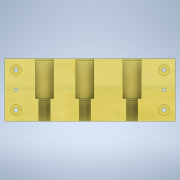
# Autodesk Inventor part: P1_V4_001_mirror
Saved by Autodesk Inventor 2020 (Build 240168000, 168)
## iProperties
Created: 2022-06-02
Part Number: P1_V4_001_mirror
Material: Wood (Maple)
Document SubType Name: Modeling
Designer: drago
Density: 0.67 g/cm^3
Appearance: Natural Maple - Glossy Dark Tint(1)
Author: drago
Autodesk Inventor part; units mm, degrees
ref_plane "YZ Plane" through (0, 0, 0) normal (1, 0, 0) x (0, 1, 0)
ref_plane "XZ Plane" through (0, 0, 0) normal (0, 1, 0) x (-1, 0, 0)
sketch "Sketch_dreptunghi_mare" plane through (0, 0, 0) normal (0, 0, 1) x (1, 0, 0)
  line L0 (0, 0) -> (-150, 0)
  line L1 (-150, 0) -> (-150, 55)
  line L2 (-150, 55) -> (0, 55)
  line L3 (0, 55) -> (0, 0)
  dimension "d77" = 150
  dimension "d78" = 55
  constraints: 8 end point, 2 parallel, 1 horizontal, 1 perpendicular
  measures "d77" distance of L1.end L2.end
  measures "d78" distance of L0.end L1.end
extrude "Extrude_monobloc" add sketch "Sketch_dreptunghi_mare" along normal blind 40
sketch "Sketch_gauri_mici_jos" plane through (-150, 55, 0) normal (0, 1, 0) x (1, 0, 0)
  line L0 (150, 0) -> (0, 0) projected
  line L1 (0, 0) -> (0, -40) projected
  line L2 (150, -40) -> (0, -40) projected
  line L3 (150, 0) -> (150, -40) projected
  line L4 (0, 0) -> (0, -40) construction
  line L5 (0, -10.5) -> (150, -10.5) construction
  line L6 (150, 0) -> (150, -40) construction
  circle A0 centre (35, -10.5) radius 7.5
  circle A1 centre (70.5, -10.5) radius 7.5
  circle A2 centre (112, -10.5) radius 7.5
  line L7 (0, 0) -> (150, 0) construction
  line L8 (15, 0) -> (15, -40) construction
  line L9 (0, -40) -> (150, -40) construction
  line L10 (135, 0) -> (135, -40) construction
  line L11 (70.5, -10.5) -> (112, -10.5) construction
  line L12 (35, -10.5) -> (35, -33.9967)
  line L13 (76.5, -33.9967) -> (70.5, -10.5)
  line L14 (112, -33.9967) -> (112, -10.5)
  dimension "d214" = 10.5
  dimension "d215" = 15
  dimension "d216" = 15
  dimension "d217" = 15
  dimension "d218" = 15
  dimension "d219" = 15
  dimension "d220" = 20
  dimension "d221" = 23
  dimension "d240" = 41.5
  constraints: 14 end point, 9 point on line, 3 centre point, 3 perpendicular, 1 collinear, 1 vertical
  measures "d214" distance between parallel lines of L5 L0
  measures "d215" diameter of A0
  measures "d216" diameter of A1
  measures "d217" diameter of A2
  measures "d218" distance between parallel lines of L1 L8
  measures "d219" distance between parallel lines of L3 L10
  measures "d220" distance from line of L8 L12.start
  measures "d221" distance from line of L10 L11.end
  measures "d240" distance of L11.end L11.start
extrude "Extrude_Cut_gauri_mici_jos" cut sketch "Sketch_gauri_mici_jos" against normal blind 20 contours A0 | A1 | A2
ref_plane "Offset_schimbare_sectiune_gauri" through (-150, 35, 40) normal (0, 1, 0) x (1, 0, 0)
sketch "Sketch_gauri_mari_sus" plane through (-150, 35, 40) normal (0, 1, 0) x (1, 0, 0)
  line L0 (150, 40) -> (0, 40) projected
  line L1 (0, 40) -> (0, 0) projected
  line L2 (150, 0) -> (0, 0) projected
  line L3 (150, 40) -> (150, 0) projected
  circle A0 centre (112, 29.5) radius 7.5 projected
  circle A1 centre (70.5, 29.5) radius 7.5 projected
  circle A2 centre (35, 29.5) radius 7.5 projected
  line L4 (150, 40) -> (0, 40) projected
  line L5 (0, 40) -> (0, 0) projected
  line L6 (150, 0) -> (0, 0) projected
  line L7 (150, 40) -> (150, 0) projected
  circle A3 centre (35, 29.5) radius 10.5
  circle A4 centre (70.5, 29.5) radius 10.5
  circle A5 centre (112, 29.5) radius 10.5
  dimension "d223" = 21
  dimension "d224" = 21
  dimension "d225" = 21
  constraints: 3 centre point, 3 concentric
  measures "d223" diameter of A3
  measures "d224" diameter of A4
  measures "d225" diameter of A5
extrude "Extrude_Cut_gauri_mari_sus" cut sketch "Sketch_gauri_mari_sus" against normal up to surface (35 mm away) contours A5 | A4 | A3 | A0 | A1 | A2
sketch "Sketch_Negrese_prins_in_perete" plane through (0, 0, 0) normal (0, 0, -1) x (-1, 0, 0)
  line L0 (0, 55) -> (150, 55) projected
  line L1 (0, 0) -> (0, 55) projected
  line L2 (150, 55) -> (150, 0) projected
  circle A0 centre (10, 10) radius 4.75
  circle A1 centre (10, 45) radius 4.75
  circle A2 centre (140, 45) radius 4.75
  circle A3 centre (140, 10) radius 4.75
  line L3 (150, 0) -> (115, 0) projected
  line L4 (38, 0) -> (0, 0) projected
  line L5 (38, 35) -> (38, 0) projected
  line L6 (79.5, 0) -> (38, 0) projected
  line L7 (79.5, 35) -> (79.5, 0) projected
  line L8 (115, 0) -> (79.5, 0) projected
  line L9 (115, 35) -> (115, 0) projected
  dimension "d127" = 9.5
  dimension "d128" = 9.5
  dimension "d129" = 9.5
  dimension "d130" = 9.5
  dimension "d131" = 10
  dimension "d134" = 10
  dimension "d136" = 10
  dimension "d138" = 10
  dimension "d189" = 10
  dimension "d190" = 10
  constraints: 4 centre point
  measures "d127" diameter of A3
  measures "d128" diameter of A2
  measures "d129" diameter of A1
  measures "d130" diameter of A0
  measures "d131" distance from line of L2 A3.centre
  measures "d134" distance from line of L2 A2.centre
  measures "d136" distance from line of L1 A0.centre
  measures "d138" distance from line of L1 A1.centre
  measures "d189" distance from line of L0 A2.centre
  measures "d190" distance from line of L0 A1.centre
extrude "Extrude_Cut_loc_cap_negrese(fixare)" cut sketch "Sketch_Negrese_prins_in_perete" against normal blind 30 contours A0 | A1 | A2 | A3
sketch "Sketch_corp_negrese_fixare_perete" plane through (0, 0, 0) normal (0, 0, -1) x (-1, 0, 0)
  circle A0 centre (10, 45) radius 4.75 projected
  circle A1 centre (140, 45) radius 4.75 projected
  circle A2 centre (10, 10) radius 4.75 projected
  circle A3 centre (140, 10) radius 4.75 projected
  line L0 (0, 55) -> (150, 55) projected
  line L1 (0, 0) -> (0, 55) projected
  line L2 (150, 55) -> (150, 0) projected
  circle A4 centre (140, 10) radius 2
  circle A5 centre (140, 45) radius 2
  circle A6 centre (10, 45) radius 2
  circle A7 centre (10, 10) radius 4.75 projected
  circle A8 centre (10, 10) radius 2
  line L3 (150, 0) -> (115, 0) projected
  line L4 (38, 0) -> (0, 0) projected
  line L5 (38, 35) -> (38, 0) projected
  line L6 (79.5, 0) -> (38, 0) projected
  line L7 (79.5, 35) -> (79.5, 0) projected
  line L8 (115, 0) -> (79.5, 0) projected
  line L9 (115, 35) -> (115, 0) projected
  dimension "d141" = 4
  dimension "d142" = 4
  dimension "d143" = 4
  dimension "d144" = 4
  constraints: 4 centre point, 4 coincident
  measures "d141" diameter of A4
  measures "d142" diameter of A5
  measures "d143" diameter of A6
  measures "d144" diameter of A8
extrude "Extrude_cut_corp_negrese(fixare)" cut sketch "Sketch_corp_negrese_fixare_perete" against normal up to next contours A4 | A5 | A6 | A8
sketch "Sketch_gaura_prins_plexi" plane through (0, 0, 0) normal (0, 0, -1) x (-1, 0, 0)
  line L0 (0, 55) -> (150, 55) projected
  line L1 (0, 0) -> (0, 55) projected
  line L2 (150, 0) -> (115, 0) projected
  circle A0 centre (10, 45) radius 4.75 projected
  circle A1 centre (10, 10) radius 4.75 projected
  circle A2 centre (140, 45) radius 4.75 projected
  circle A3 centre (140, 10) radius 4.75 projected
  line L3 (150, 55) -> (150, 0) projected
  line L4 (0, 55) -> (150, 55) projected
  circle A4 centre (10, 45) radius 2 construction
  circle A5 centre (140, 10) radius 2 construction
  circle A6 centre (140, 45) radius 2 construction
  circle A7 centre (140, 27.5) radius 1.7
  circle A8 centre (10, 27.5) radius 1.7
  line L5 (150, 55) -> (150, 0) projected
  line L6 (150, 0) -> (115, 0) projected
  line L7 (0, 0) -> (0, 55) projected
  line L8 (10, 45) -> (10, 27.5) construction
  line L9 (10, 10) -> (10, 27.5) construction
  circle A9 centre (140, 45) radius 2 construction
  line L10 (140, 45) -> (140, 27.5) construction
  circle A10 centre (140, 10) radius 2 construction
  line L11 (140, 27.5) -> (140, 10) construction
  line L12 (38, 0) -> (0, 0) projected
  line L13 (38, 35) -> (38, 0) projected
  line L14 (79.5, 0) -> (38, 0) projected
  line L15 (79.5, 35) -> (79.5, 0) projected
  line L16 (115, 0) -> (79.5, 0) projected
  line L17 (115, 35) -> (115, 0) projected
  line L18 (38, 0) -> (0, 0) projected
  line L19 (38, 35) -> (38, 0) projected
  line L20 (79.5, 0) -> (38, 0) projected
  line L21 (79.5, 35) -> (79.5, 0) projected
  line L22 (115, 0) -> (79.5, 0) projected
  line L23 (115, 35) -> (115, 0) projected
  dimension "d155" = 3.4
  dimension "d156" = 3.4
  constraints: 8 end point, 3 collinear, 3 vertical, 2 centre point, 1 coincident
  measures "d155" diameter of A7
  measures "d156" diameter of A8
extrude "Extrude_cut_gaura_prins_plexi" cut sketch "Sketch_gaura_prins_plexi" against normal up to surface (40 mm away) contours A7 | A8
sketch "deschiderea_sa_se_vada_cuiele" plane through (0, 0, 0) normal (0, 0, -1) x (-1, 0, 0)
  line L0 (125.5, 0) -> (104.5, 0) projected
  line L1 (90, 0) -> (69, 0) projected
  line L2 (48.5, 0) -> (27.5, 0) projected
  line L3 (125.5, 35) -> (104.5, 35) projected
  line L4 (90, 35) -> (69, 35) projected
  line L5 (48.5, 35) -> (27.5, 35) projected
  line L6 (104.5, 0) -> (125.5, 0)
  line L7 (150, 0) -> (115, 0) construction
  line L8 (125.5, 35) -> (104.5, 35)
  line L9 (107, 35) -> (123, 35)
  line L10 (123, 35) -> (123, 0)
  line L11 (123, 0) -> (107, 0)
  line L12 (107, 0) -> (107, 35)
  line L13 (107, 35) -> (123, 0)
  line L14 (123, 35) -> (107, 0)
  line L15 (115, 0) -> (79.5, 0) projected
  line L16 (115, 0) -> (115, 17.5)
  line L17 (115, 35) -> (115, 0) projected
  line L18 (115, 35) -> (115, 17.5)
  line L19 (71.5, 35) -> (87.5, 35)
  line L20 (87.5, 35) -> (87.5, 0)
  line L21 (87.5, 0) -> (71.5, 0)
  line L22 (71.5, 0) -> (71.5, 35)
  line L23 (79.5, 35) -> (79.5, 0) projected
  line L24 (71.5, 35) -> (87.5, 0)
  line L25 (87.5, 35) -> (71.5, 0)
  line L26 (79.5, 0) -> (38, 0) projected
  line L27 (30, 35) -> (46, 35)
  line L28 (46, 35) -> (46, 0)
  line L29 (46, 0) -> (30, 0)
  line L30 (30, 0) -> (30, 35)
  line L31 (38, 35) -> (38, 0) projected
  line L32 (30, 35) -> (46, 0)
  line L33 (46, 35) -> (30, 0)
  point P0 (79.5, 17.5)
  point P1 (38, 17.5)
  point P2 (30, 35)
  point P3 (30, 0)
  point P4 (46, 0)
  point P5 (87.5, 0)
  point P6 (71.5, 35)
  point P7 (71.5, 0)
  point P8 (123, 0)
  point P9 (123, 35)
  point P10 (107, 35)
  point P11 (107, 0)
  dimension "d227" = 16
  dimension "d228" = 16
  dimension "d229" = 16
  constraints: 44 end point, 8 midpoint, 7 parallel, 4 collinear, 3 horizontal, 3 perpendicular, 3 point on line
  measures "d227" distance of L10.end L11.end
  measures "d228" distance of L20.end L21.end
  measures "d229" distance of L28.end L29.end
extrude "Extrude_sa_se_vada_cuiele" cut sketch "deschiderea_sa_se_vada_cuiele" against normal blind 5
sketch "Sketch17" plane through (0, 0, 40) normal (0, 0, 1) x (1, 0, 0)
  circle A0 centre (-10, 27.5) radius 1.7
  circle A1 centre (-140, 27.5) radius 1.7 projected
  circle A2 centre (-10, 45) radius 2 projected
  circle A3 centre (-140, 45) radius 2 projected
  circle A4 centre (-10, 10) radius 2 projected
  circle A5 centre (-140, 10) radius 2 projected
  line L0 (0, 55) -> (-150, 55) projected
  line L1 (-150, 55) -> (-150, 0) projected
  line L2 (-150, 0) -> (0, 0) projected
  line L3 (0, 0) -> (0, 55) projected
  line L4 (-19.75, 5) -> (-130.25, 5)
  line L5 (-130.25, 5) -> (-130.25, 50)
  line L6 (-130.25, 50) -> (-19.75, 50)
  line L7 (-19.75, 50) -> (-19.75, 5)
  circle A6 centre (-10, 45) radius 2 projected
  circle A7 centre (-10, 10) radius 2 projected
  circle A8 centre (-10, 45) radius 4.75 projected
  circle A9 centre (-140, 45) radius 4.75 projected
  dimension "d181" = 5
  dimension "d182" = 5
  dimension "d236" = 9.75
  dimension "d237" = 9.75
  constraints: 8 end point, 2 parallel, 1 centre point, 1 horizontal, 1 perpendicular
  measures "d181" distance between parallel lines of L4 L2
  measures "d182" distance between parallel lines of L0 L6
  measures "d236" distance from line of L5 A9.centre
  measures "d237" distance from line of A8.centre L7
extrude "Extrude_cut_gaura_mare_in_spate" cut sketch "Sketch17" against normal blind 14 contours L4 L5 L6 L7
sketch "Sketch20" plane through (0, 0, 0) normal (0, 0, -1) x (-1, 0, 0)
  line L0 (107.5, 55) -> (122.5, 55) projected
  line L1 (72, 55) -> (87, 55) projected
  line L2 (30.5, 55) -> (45.5, 55) projected
  line L3 (107, 35) -> (123, 35) construction
  line L4 (115, 35) -> (115, 55) construction
  line L5 (71.5, 35) -> (87.5, 35) construction
  line L6 (79.5, 35) -> (79.5, 55) construction
  line L7 (30, 35) -> (46, 35) construction
  line L8 (38, 35) -> (38, 55) construction
  line L9 (0, 55) -> (150, 55) construction
  line L10 (110, 55) -> (120, 55)
  line L11 (120, 55) -> (120, 35)
  line L12 (120, 35) -> (110, 35)
  line L13 (110, 35) -> (110, 55)
  line L14 (110, 55) -> (120, 35) construction
  line L15 (120, 55) -> (110, 35) construction
  line L16 (74.5, 55) -> (84.5, 55)
  line L17 (84.5, 55) -> (84.5, 35)
  line L18 (84.5, 35) -> (74.5, 35)
  line L19 (74.5, 35) -> (74.5, 55)
  line L20 (74.5, 55) -> (84.5, 35) construction
  line L21 (84.5, 55) -> (74.5, 35) construction
  line L22 (33, 55) -> (43, 55)
  line L23 (43, 55) -> (43, 35)
  line L24 (43, 35) -> (33, 35)
  line L25 (33, 35) -> (33, 55)
  line L26 (33, 55) -> (43, 35) construction
  line L27 (43, 55) -> (33, 35) construction
  point P0 (0, 0)
  point P1 (115, 45)
  point P2 (79.5, 45)
  point P3 (38, 45)
  point P4 (84.5, 55)
  point P5 (74.5, 55)
  point P6 (120, 55)
  point P7 (110, 55)
  dimension "d230" = 10
  dimension "d231" = 10
  dimension "d232" = 10
  constraints: 42 end point, 14 midpoint, 8 parallel, 3 horizontal, 3 perpendicular, 3 point on line, 2 other
  measures "d230" distance of L11.end L12.end
  measures "d231" distance of L17.end L18.end
  measures "d232" distance of L23.end L24.end
extrude "Extrusion16" cut sketch "Sketch20" against normal blind 5
fillet "Fillet9" radius 2 6 edges at (-115, 35, 18) (-115, 0, 21) (-79.5, 35, 18) (-79.5, 0, 21) (-38, 35, 18) (-38, 0, 21)
body "Solid3"
